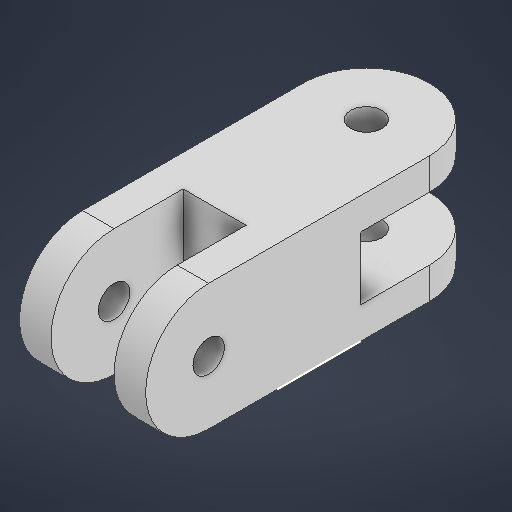
# Autodesk Inventor part: Peça1
Saved by Autodesk Inventor 2026.2 (Build 302298000, 298)
## iProperties
Created: 2026-07-31
Part Number: Peça1
Material: Genérico
Document SubType Name: Modeling
Designer: IFSP
Density: 1 g/cm^3
Appearance: Padrão
Author: IFSP
Autodesk Inventor part; units mm, degrees
ref_plane "YZ Plane" through (0, 0, 0) normal (1, 0, 0) x (0, 1, 0)
ref_plane "XZ Plane" through (0, 0, 0) normal (0, 1, 0) x (-1, 0, 0)
ref_plane "XY Plane" through (0, 0, 0) normal (0, 0, 1) x (1, 0, 0)
sketch "Esboço1" plane through (0, 0, 0) normal (0, 0, 1) x (1, 0, 0)
  point P0 (0, 0)
sketch "Esboço2" plane through (0, 0, 0) normal (1, 0, 0) x (0, 1, 0)
  line L0 (0, 0) -> (0, -42)
  line L1 (0, -42) -> (64, -42)
  line L2 (64, -42) -> (64, 0)
  line L3 (64, 0) -> (0, 0)
  dimension "d12" = 42
  dimension "d13" = 64
  constraints: 8 end point, 3 perpendicular, 1 vertical
  measures "d12" distance of L1.end L2.end
  measures "d13" distance of L0.end L1.end
extrude "Extrusão1" add sketch "Esboço2" along normal blind 64
sketch "Esboço3" plane through (64, 0, 0) normal (1, 0, 0) x (0, 0, -1)
  line L0 (0, 0) -> (42, 0) projected
  line L1 (0, 0) -> (42, 0)
  constraints: 2 end point, 1 horizontal
sketch "Esboço4" plane through (64, 0, 0) normal (1, 0, 0) x (0, 0, -1)
  line L0 (0, 64) -> (0, 0) projected
  line L1 (0, 0) -> (-35, 0)
  line L2 (-35, 0) -> (-35, 64)
  line L3 (-35, 64) -> (0, 64)
  circle A0 centre (-35, 32) radius 32
  dimension "d16" = 35
  dimension "d17" = 64
  constraints: 6 end point, 2 perpendicular, 1 centre point, 1 horizontal, 1 midpoint
  measures "d16" distance of L0.end L1.end
  measures "d17" diameter of A0
extrude "Extrusão2" add sketch "Esboço4" against normal blind 16
sketch "Esboço5" plane through (0, 0, 0) normal (-1, 0, 0) x (0, 0, 1)
  line L0 (-42, 0) -> (-42, 64) projected
  line L1 (-42, 64) -> (35, 64) projected
  line L2 (-42, 64) -> (35, 64)
  arc A0 (35, 0) -> (35, 64) centre (35, 32) ccw projected
  line L3 (35, 64) -> (35, 0)
  line L4 (35, 0) -> (-42, 0) projected
  line L5 (35, 0) -> (-42, 0)
  line L6 (-42, 0) -> (-42, 64)
  circle A1 centre (35, 32) radius 32
  line L7 (0, 64) -> (0, 0) projected
  line L8 (0, 64) -> (0, 0)
  constraints: 10 end point, 3 perpendicular, 1 centre point, 1 coincident, 1 collinear, 1 concentric, 1 horizontal
extrude "Extrusão3" add sketch "Esboço5" against normal blind 16 contours L7 L1 A1 L4 | L3 A0 | A1 L3
sketch "Esboço6" plane through (0, 0, 0) normal (-1, 0, 0) x (0, 0, 1)
  line L0 (0, 64) -> (0, 0) projected
  circle A0 centre (35, 32) radius 8
  dimension "d24" = 16
  constraints: 1 centre point
  measures "d24" diameter of A0
extrude "Extrusão4" cut sketch "Esboço6" against normal blind 64
sketch "Esboço7" plane through (0, 64, -42) normal (0, 1, 0) x (1, 0, 0)
  line L0 (0, 0) -> (0, -77) projected
  line L1 (0, 0) -> (0, 35)
  line L2 (0, 35) -> (64, 35)
  line L3 (0, 0) -> (64, 0) projected
  line L4 (64, 35) -> (64, 0)
  circle A0 centre (32, 35) radius 32
  point P0 (0, -42)
  dimension "d27" = 35
  dimension "d28" = 64
  dimension "d29" = 64
  constraints: 6 end point, 1 centre point, 1 midpoint, 1 perpendicular, 1 vertical
  measures "d27" distance of L0.start L1.end
  measures "d28" distance of L1.end L2.end
  measures "d29" diameter of A0
extrude "Extrusão5" add sketch "Esboço7" against normal blind 16
sketch "Esboço8" plane through (0, 0, -42) normal (0, -1, 0) x (1, 0, 0)
  line L0 (0, 0) -> (64, 0) projected
  line L1 (64, 77) -> (64, -35) projected
  line L2 (64, 0) -> (64, -35)
  arc A0 (0, -35) -> (64, -35) centre (32, -35) ccw projected
  line L3 (64, -35) -> (0, -35)
  line L4 (0, -35) -> (0, 0)
  circle A1 centre (32, -35) radius 32
  point P0 (0, 42)
  constraints: 6 end point, 2 perpendicular, 1 centre point, 1 coincident, 1 collinear, 1 concentric, 1 tangent
extrude "Extrusão6" add sketch "Esboço8" against normal blind 16
sketch "Esboço9" plane through (48, 0, 35) normal (0, -1, 0) x (1, 0, 0)
  line L0 (16, 0) -> (16, -112) projected
  circle A0 centre (-16, -112) radius 8
  point P0 (-48, -35)
  dimension "d35" = 16
  constraints: 1 centre point
  measures "d35" diameter of A0
extrude "Extrusão7" cut sketch "Esboço9" against normal blind 64
